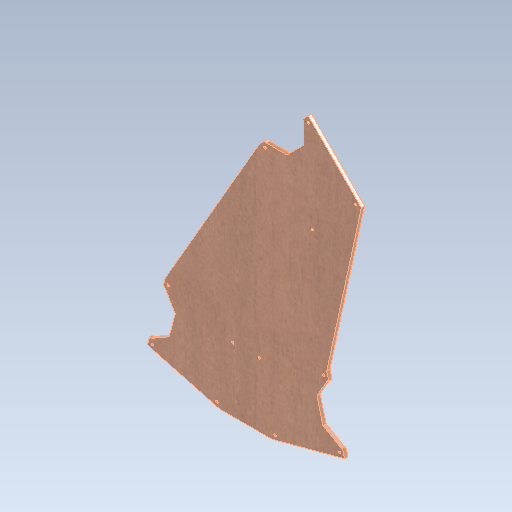
# Autodesk Inventor part: wdfs_mcnm1_top
Saved by Autodesk Inventor 2027.1 (Build 311270010, 270A)
## iProperties
Created: 2026-10-20
Part Number: wdfs_mcnm1_top
Material: ラワン材、メランティ
Document SubType Name: Modeling
Designer: ug_nd
Density: 0.416 g/cm^3
Appearance: マホガニー材 - 硬質 塗装 濃い色 標準の光沢
Author: ug_nd
Autodesk Inventor part; units mm, degrees
ref_plane "YZ Plane" through (0, 0, 0) normal (1, 0, 0) x (0, 1, 0)
ref_plane "XZ Plane" through (0, 0, 0) normal (0, 1, 0) x (-1, 0, 0)
ref_plane "XY Plane" through (0, 0, 0) normal (0, 0, 1) x (1, 0, 0)
sketch "スケッチ1" plane through (0, 0, 0) normal (0, 0, 1) x (1, 0, 0)
  line L0 (0, -280) -> (0, 280) construction
  circle A0 centre (0, 0) radius 200 construction
  line L1 (0, 200) -> (111.3693, 88.6307) construction
  line L2 (-21.0718, -140.764) -> (-173.2051, -100) construction
  line L3 (-173.2051, -100) -> (0, 0) construction
  line L4 (-98.9371, -75.9008) -> (-120.9367, -158.0045)
  line L5 (-120.9367, -158.0045) -> (-32.0716, -181.8158)
  line L6 (98.9371, -75.9008) -> (120.9367, -158.0045)
  line L7 (120.9367, -158.0045) -> (32.0716, -181.8158)
  line L8 (-32.0716, -181.8158) -> (32.0716, -181.8158)
  line L9 (173.2051, -100) -> (0, 0) construction
  line L10 (16.2635, 123.6325) -> (76.3675, 183.7365)
  line L11 (76.3675, 183.7365) -> (141.4214, 118.6827)
  line L12 (16.2635, 123.6325) -> (-98.9371, -75.9008)
  line L13 (141.4214, 118.6827) -> (98.9371, -75.9008)
  circle A1 centre (-114.813, -154.469) radius 1.5
  circle A2 centre (-35.6071, -175.6921) radius 1.5
  circle A3 centre (-16.1957, -103.2477) radius 1.5
  circle A4 centre (-95.4016, -82.0245) radius 1.5
  line L14 (-98.9371, -75.9008) -> (-10.072, -99.7122) construction
  line L15 (-10.072, -99.7122) -> (-32.0716, -181.8158) construction
  circle A5 centre (114.813, -154.469) radius 1.5
  circle A6 centre (35.6071, -175.6921) radius 1.5
  circle A7 centre (16.1957, -103.2477) radius 1.5
  circle A8 centre (95.4016, -82.0245) radius 1.5
  circle A9 centre (76.3675, 176.6655) radius 1.5
  circle A10 centre (134.3503, 118.6827) radius 1.5
  circle A11 centre (81.3173, 65.6497) radius 1.5
  circle A12 centre (23.3345, 123.6325) radius 1.5
  dimension "d1" = 400
  dimension "d6" = 120
  dimension "d10" = 45
  dimension "d12" = 45
  dimension "d13" = 157.5
  dimension "d14" = 65.5
  dimension "d15" = 85
  dimension "d16" = 92
  dimension "d17" = 5
  dimension "d18" = 5
  dimension "d19" = 3
  dimension "d20" = 5
  dimension "d21" = 5
  dimension "d22" = 5
  dimension "d23" = 5
  dimension "d24" = 5
  dimension "d25" = 5
  constraints: 30 end point, 16 symmetric about line, 13 centre point, 4 perpendicular, 3 equal radius, 2 point on circle, 1 coincident, 1 equal length, 1 horizontal, 1 point on line, 8 other
  measures "d1" diameter of A0
  measures "d6" angle of L3 L0
  measures "d10" angle of L2 L3
  measures "d12" angle of L0 L1
  measures "d13" distance of L2.start L2.end
  measures "d14" distance from line of L4 L2.end
  measures "d15" distance of L4.start L4.end
  measures "d16" distance of L4.end L5.end
  measures "d17" distance from line of A1.centre L4
  measures "d18" distance from line of L5 A1.centre
  measures "d19" diameter of A1
  measures "d20" distance from line of L5 A2.centre
  measures "d21" distance from line of L15 A2.centre
  measures "d22" distance from line of L15 A3.centre
  measures "d23" distance from line of L14 A3.centre
  measures "d24" distance from line of L14 A4.centre
  measures "d25" distance from line of L4 A4.centre
extrude "押し出し1" add sketch "スケッチ1" along normal mid plane 4
sketch "スケッチ2" plane through (0, 0, 2) normal (0, 0, 1) x (1, 0, 0)
  line L0 (-98.9371, -75.9008) -> (-120.9367, -158.0045) construction
  line L1 (-120.9367, -158.0045) -> (-32.0716, -181.8158) construction
  line L2 (-32.0716, -181.8158) -> (32.0716, -181.8158) construction
  line L3 (32.0716, -181.8158) -> (120.9367, -158.0045) construction
  line L4 (120.9367, -158.0045) -> (98.9371, -75.9008) construction
  line L5 (98.9371, -75.9008) -> (141.4214, 118.6827) construction
  line L6 (141.4214, 118.6827) -> (76.3675, 183.7365) construction
  line L7 (76.3675, 183.7365) -> (16.2635, 123.6325) construction
  line L8 (16.2635, 123.6325) -> (-98.9371, -75.9008) construction
  circle A0 centre (-16.1957, -103.2477) radius 1.5 construction
  circle A1 centre (-95.4016, -82.0245) radius 1.5 construction
  circle A2 centre (95.4016, -82.0245) radius 1.5 construction
  circle A3 centre (16.1957, -103.2477) radius 1.5 construction
  circle A4 centre (81.3173, 65.6497) radius 1.5 construction
  circle A5 centre (134.3503, 118.6827) radius 1.5 construction
  circle A6 centre (76.3675, 176.6655) radius 1.5 construction
  circle A7 centre (23.3345, 123.6325) radius 1.5 construction
  circle A8 centre (35.6071, -175.6921) radius 1.5 construction
  circle A9 centre (114.813, -154.469) radius 1.5 construction
  circle A10 centre (-35.6071, -175.6921) radius 1.5 construction
  circle A11 centre (-114.813, -154.469) radius 1.5 construction
  line L9 (23.3345, 130.7035) -> (24.7487, 129.2893)
  line L10 (50.2046, 129.2893) -> (70.7107, 149.7954)
  line L11 (70.7107, 175.2513) -> (69.2965, 176.6655)
  line L12 (23.3345, 130.7035) -> (69.2965, 176.6655)
  line L13 (24.7487, 129.2893) -> (50.2046, 129.2893)
  line L14 (70.7107, 175.2513) -> (70.7107, 149.7954)
  line L15 (118.3486, -148.3452) -> (116.4167, -148.8629)
  line L16 (94.3713, -136.135) -> (86.8655, -108.1231)
  line L17 (99.5935, -86.0777) -> (101.5253, -85.5601)
  line L18 (101.5253, -85.5601) -> (118.3486, -148.3452)
  line L19 (94.3713, -136.135) -> (116.4167, -148.8629)
  line L20 (99.5935, -86.0777) -> (86.8655, -108.1231)
  line L21 (-101.5253, -85.5601) -> (-99.5935, -86.0777)
  line L22 (-86.8655, -108.1231) -> (-94.3713, -136.135)
  line L23 (-116.4167, -148.8629) -> (-118.3486, -148.3452)
  line L24 (-118.3486, -148.3452) -> (-101.5253, -85.5601)
  line L25 (-99.5935, -86.0777) -> (-86.8655, -108.1231)
  line L26 (-116.4167, -148.8629) -> (-94.3713, -136.135)
  point P0 (0, 0)
  point P1 (37.4767, 116.5614)
  point P2 (83.4386, 162.5233)
  point P3 (99.03, -153.5216)
  point P4 (82.2068, -90.7364)
  point P5 (-82.2068, -90.7364)
  point P6 (-99.03, -153.5216)
  dimension "d29" = 18
  dimension "d30" = 18
  dimension "d31" = 18
  dimension "d32" = 18
  dimension "d35" = 20
  dimension "d36" = 18
  dimension "d37" = 18
  dimension "d38" = 18
  dimension "d39" = 18
  dimension "d43" = 18
  dimension "d44" = 18
  dimension "d45" = 18
  dimension "d46" = 18
  dimension "d49" = 20
  dimension "d50" = 10
  dimension "d51" = 10
  dimension "d52" = 20
  dimension "d53" = 10
  dimension "d54" = 10
  dimension "d55" = 10
  dimension "d56" = 10
  constraints: 36 end point, 18 point on line, 9 perpendicular
  measures "d29" distance of L9.end point (37.477, 116.561)
  measures "d30" distance of L10.start point (37.477, 116.561)
  measures "d31" distance of L11.start point (83.439, 162.523)
  measures "d32" distance of L10.end point (83.439, 162.523)
  measures "d35" distance between parallel lines of L18 L16
  measures "d36" distance of L16.start point (99.03, -153.522)
  measures "d37" distance of L15.end point (99.03, -153.522)
  measures "d38" distance of L17.start point (82.207, -90.736)
  measures "d39" distance of L16.end point (82.207, -90.736)
  measures "d43" distance of L21.end point (-82.207, -90.736)
  measures "d44" distance of L22.start point (-82.207, -90.736)
  measures "d45" distance of L23.start point (-99.03, -153.522)
  measures "d46" distance of L22.end point (-99.03, -153.522)
  measures "d49" distance between parallel lines of L10 L12
  measures "d50" distance between parallel lines of L6 L11
  measures "d51" distance from line of L7.end L9
  measures "d52" distance between parallel lines of L24 L22
  measures "d53" distance from line of L21 L0.start
  measures "d54" distance between parallel lines of L1 L23
  measures "d55" distance from line of L17 L4.end
  measures "d56" distance between parallel lines of L3 L15
extrude "押し出し2" cut sketch "スケッチ2" against normal blind 10
equation "\"d30\" = d29"
equation "\"d31\" = d29"
equation "\"d32\" = d31"
equation "\"d35\" = d26"
equation "\"d36\" = d29"
equation "\"d37\" = d36"
equation "\"d38\" = d36"
equation "\"d39\" = d38"
equation "\"d43\" = d29"
equation "\"d44\" = d43"
equation "\"d45\" = d43"
equation "\"d46\" = d45"
equation "\"d51\" = d50"
equation "\"d26\" = 20"
